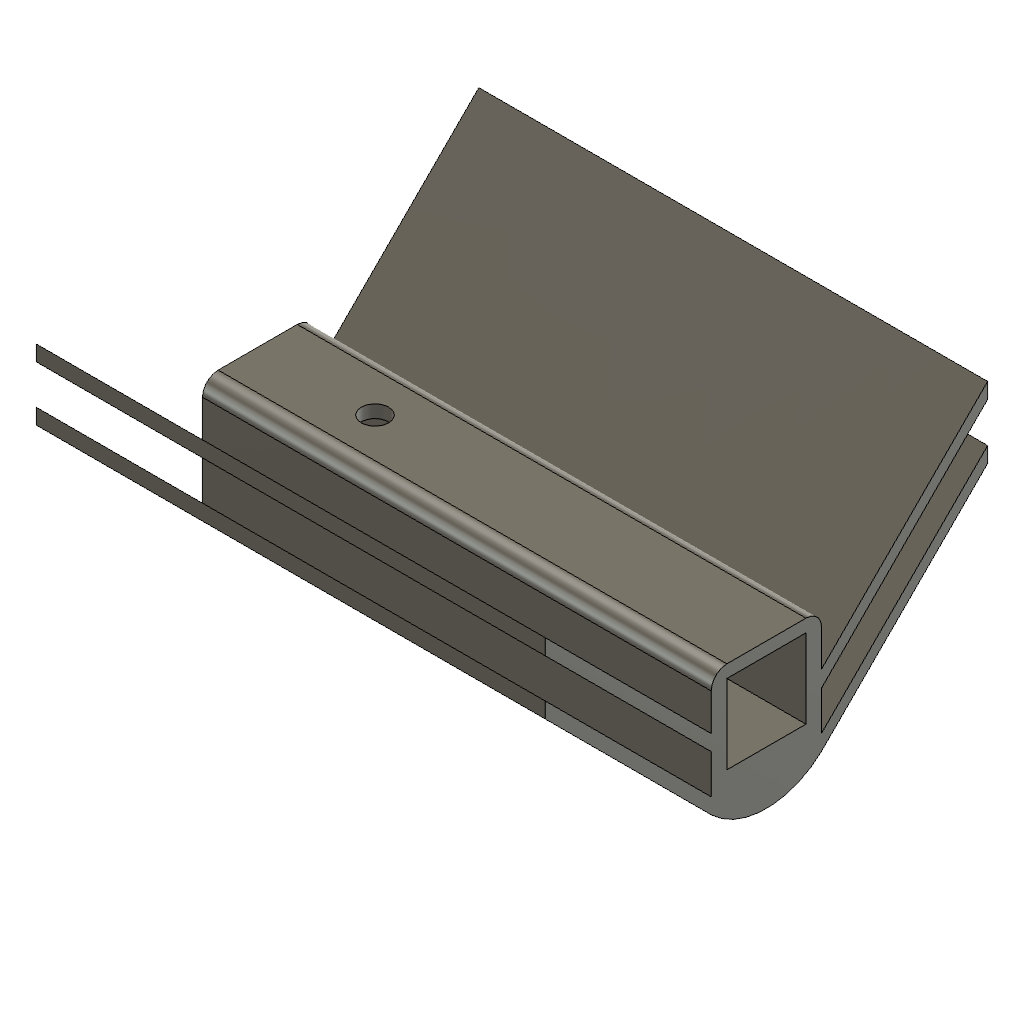
rc-airplanes-trainer-airplane-fusion-parts-empannage-clip-v-tail-45-foam (Autodesk Fusion 360 design; units mm, degrees)
Autodesk Fusion 360 part; units mm, degrees
sketch "Sketch1" plane through (0, 0, 0) normal (1, 0, 0) x (0, 0, -1)
  line L0 (-12.95, 7.55) -> (-12.95, -2.55)
  line L1 (-23.05, 7.55) -> (-12.95, 7.55)
  line L2 (-12.95, 7.55) -> (-12.95, -2.55)
  line L3 (-23.05, 7.55) -> (-12.95, 7.55)
  line L4 (-12.95, -2.55) -> (-23.05, -2.55)
  line L5 (-10.9506, 9.175) -> (-25.0494, 9.175)
  line L6 (-25.0494, -4.5393) -> (-46.2626, 16.674)
  line L7 (-25.0494, 0.4607) -> (-46.2626, 21.674)
  line L8 (-12.95, -2.55) -> (-23.05, -2.55)
  line L9 (-25.0494, 9.175) -> (-10.9506, 9.175)
  line L10 (-23.05, -2.55) -> (-23.05, 7.55)
  line L11 (-23.05, -2.55) -> (-23.05, 7.55)
  line L12 (-10.9506, -4.5393) -> (10.2626, 16.674)
  line L13 (-25.0494, -6.5393) -> (-46.2626, 14.674)
  line L14 (-25.0494, -6.5393) -> (4.9506, -6.5393) construction
  line L15 (-10.9506, -6.5393) -> (10.2626, 14.674)
  arc A0 (-25.0494, -6.5393) -> (-10.9506, -6.5393) centre (-18, 0.8018) ccw
  line L16 (10.2626, 16.674) -> (10.2626, 14.674)
  line L17 (-46.2626, 16.674) -> (-46.2626, 14.674)
  line L18 (-46.2626, 21.674) -> (-46.2626, 23.674)
  line L19 (-25.0494, 2.4607) -> (-46.2626, 23.674)
  line L20 (10.2626, 21.7668) -> (10.2626, 23.7668)
  line L21 (10.2626, 23.7668) -> (-10.9506, 2.5536)
  line L22 (-10.9506, -4.5393) -> (-10.9506, 0.4607)
  line L23 (-10.9506, 0.4607) -> (10.2626, 21.7668)
  line L24 (-10.9506, 2.5536) -> (-10.9506, 9.175)
  line L25 (-25.0494, 9.175) -> (-25.0494, 2.4607)
  line L26 (-25.0494, 0.4607) -> (-25.0494, -4.5393)
  dimension "d8" = 30
  dimension "d16" = 2
  dimension "d17" = 2
  dimension "d18" = 135
  dimension "d19" = 30
  dimension "d21" = 30
  dimension "d36" = 2
  dimension "d37" = 2
  dimension "d39" = 2
  dimension "d46" = 5
  constraint coincident L5.end L9.start
  constraint coincident L0.end L2.end
  constraint coincident L1.start L3.start
  constraint vertical L18
  constraint vertical L20
  constraint perpendicular L5 L24
  constraint perpendicular L5 L25
  constraint collinear L25 L26
  measures "d8" distance of L12.end L12.start
  measures "d16" distance of L6.start L13.start
  measures "d17" distance of L12.start L15.start
  measures "d18" angle of L13 L14
  measures "d19" distance of L13.start L13.end
  measures "d21" distance of L15.start L15.end
  measures "d36" distance of L7.start L19.start
  measures "d37" distance of L7.end L18.end
  measures "d39" distance of L20.start L20.end
  measures "d46" distance of L12.start L22.end
sketch "Sketch2" plane through (0, 9.175, 0) normal (0, 1, 0) x (-1, 0, 0)
  line L0 (0, 10.9506) -> (0, 25.0494)
  line L1 (0, 25.0494) -> (-65, 25.0494)
  line L2 (-65, 25.0494) -> (-65, 10.9506)
  line L3 (-65, 10.9506) -> (0, 10.9506)
  circle A0 centre (-15, 18) radius 1.75
extrude "Extrude9" add sketch "Sketch1" along normal blind 65
extrude "Extrude10" cut sketch "Sketch2" against normal blind 25 contours A0
fillet "Fillet2" radius 2 2 edges at (32.5, 9.175, 10.9506) (32.5, 9.175, 25.0494)
extrude "Extrude6" [suppressed]
extrude "Extrude7" [suppressed]
extrude "Extrude8" [suppressed]
